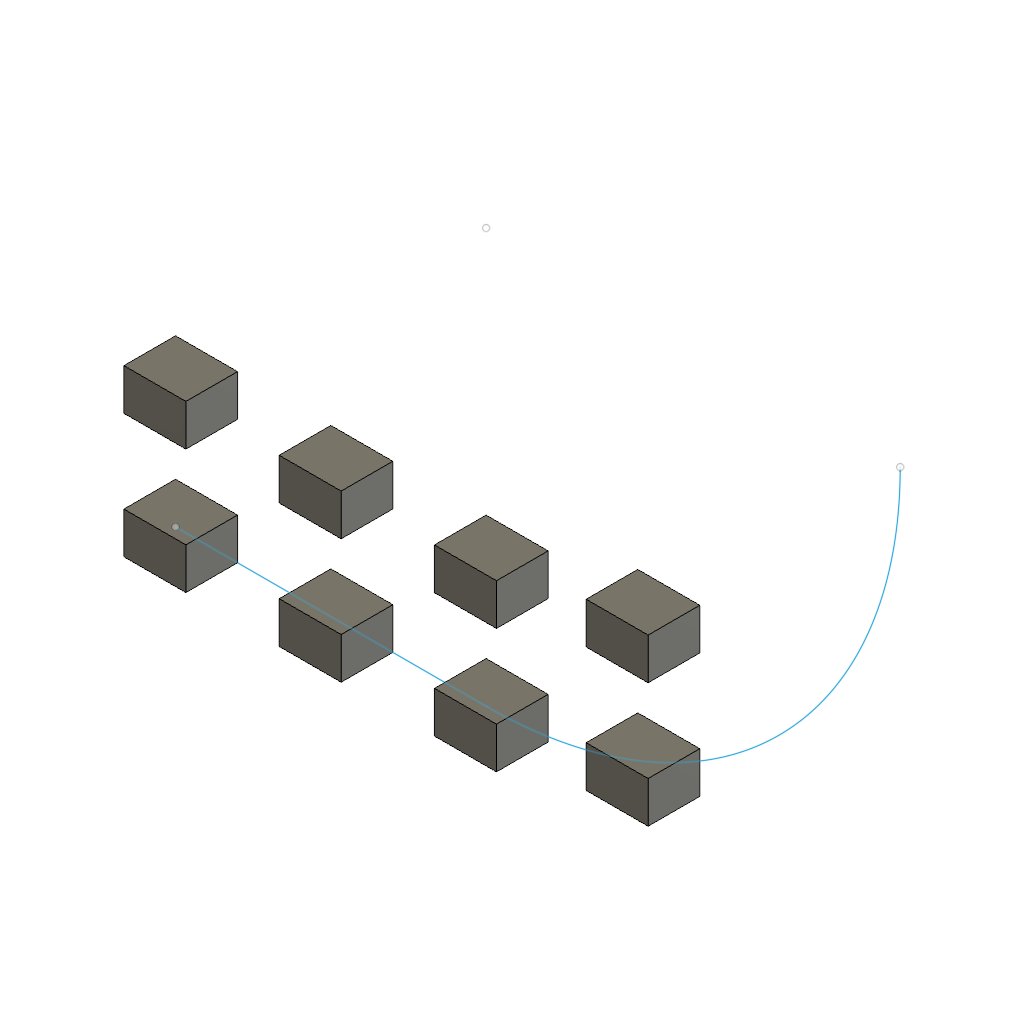
composite_multiple (Autodesk Fusion 360 design; units mm, degrees)
part number: 2026-10-20-22-51-27-170
Autodesk Fusion 360 part; units mm, degrees
sketch "PatternSeedSketch0" plane through (0, 0, 0) normal (0, 0, 1) x (1, 0, 0)
  line L0 (0, 0) -> (6, 0)
  line L1 (6, 0) -> (6, 4)
  line L2 (6, 4) -> (0, 4)
  line L3 (0, 4) -> (0, 0)
extrude "PatternSeedFeature0" add sketch "PatternSeedSketch0" along normal blind 5 makes body 1
sketch "PatternSeedSketch1" plane through (0, 0, 0) normal (0, 0, 1) x (1, 0, 0)
  line L0 (0, 12) -> (6, 12)
  line L1 (6, 12) -> (6, 16)
  line L2 (6, 16) -> (0, 16)
  line L3 (0, 16) -> (0, 12)
extrude "PatternSeedFeature1" add sketch "PatternSeedSketch1" along normal blind 5 separate body makes body 2
sketch "CompositePatternPath" plane through (0, 0, 0) normal (0, 0, 1) x (1, 0, 0)
  line L0 (0, 0) -> (30, 0)
  arc A0 (30, 0) -> (70, 40) centre (30, 40) ccw
pattern_path "ProbeCompositePathPattern" count 4 spacing 15 from (0, 0, 0) path "CompositePatternPath" along L0 A0 of bodies 1 2 makes body 3 at (19, 4, 1.6667) makes body 4 at (34, 4, 1.6667) makes body 5 at (48.6509, 6.7797, 1.6667) makes body 6 at (19, 16, 1.6667) makes body 7 at (34, 16, 1.6667) makes body 8 at (48.6509, 18.7797, 1.6667)
named bodies: "PatternSeedBody0", "PatternSeedBody1", "PatternSeedBody0 (1)", "PatternSeedBody0 (2)", "PatternSeedBody0 (3)", "PatternSeedBody1 (1)", "PatternSeedBody1 (2)", "PatternSeedBody1 (3)"
